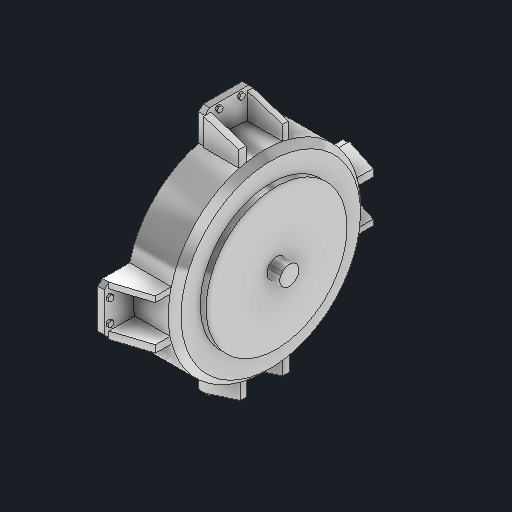
# Autodesk Inventor part: Bauteil1
Saved by Autodesk Inventor 2027.1 (Build 311270010, 270A)
## iProperties
Part Number: Bauteil1
Material: Generisch
Document SubType Name: Modellieren
Designer: Asus
Density: 1 g/cm^3
Appearance: Chrom - poliert
Author: Asus
Autodesk Inventor part; units mm, degrees
ref_plane "YZ-Ebene" through (0, 0, 0) normal (1, 0, 0) x (0, 1, 0)
ref_plane "XZ-Ebene" through (0, 0, 0) normal (0, 1, 0) x (-1, 0, 0)
sketch "Skizze1" plane through (0, 0, 0) normal (0, 0, 1) x (1, 0, 0)
  circle A0 centre (0, 0) radius 150
  dimension "d0" = 300
  constraints: 1 centre point, 1 coincident
  measures "d0" diameter of A0
extrude "Extrusion1" add sketch "Skizze1" along normal blind 75
chamfer "Fasen1" distance 10 angle 45 1 edges at (-150, 0, 75)
sketch "Skizze2" plane through (0, 0, 0) normal (0, 0, 1) x (1, 0, 0)
  circle A0 centre (0, 0) radius 150 projected
  line L0 (-37.5, 194.6569) -> (37.5, 194.6569)
  line L1 (37.5, 194.6569) -> (37.5, 145.2369)
  line L2 (-37.5, 145.2369) -> (-37.5, 194.6569)
  point P0 (0, 194.6569)
  dimension "d6" = 75
  dimension "d7" = 49.42
  constraints: 6 end point, 2 point on circle, 1 horizontal, 1 midpoint, 1 parallel, 1 perpendicular, 1 vertical alignment
  measures "d6" distance of L0.start L0.end
  measures "d7" distance of L0.end L1.end
extrude "Extrusion2" add sketch "Skizze2" along normal blind 10 contours A0 L2 L0 L1
chamfer "Fasen2" distance 7 angle 45 1 edges at (37.5, 194.6569, 5) measured on face at (37.5, 194.1569, 5)
chamfer "Fasen3" distance 7 angle 45 1 edges at (-37.5, 194.6569, 5) measured on face at (-37.5, 194.1569, 5)
sketch "Skizze3" plane through (-37.5, 145.2369, 0) normal (-1, 0, 0) x (0, 0, 1)
  line L0 (0, 42.42) -> (10, 42.42) projected
  line L1 (0, 42.42) -> (0, 0) projected
  line L2 (10, 0) -> (0, 0) projected
  line L3 (10, 42.42) -> (10, 0) projected
  line L4 (10, 0) -> (65, 0)
  line L5 (75, -10.3527) -> (75, -280.1211) construction
  line L6 (65, -290.4738) -> (0, -290.4738) construction
  line L7 (0, -290.4738) -> (0, 0) construction
  line L8 (0, 0) -> (0, 42.42) construction
  line L9 (0, 42.42) -> (10, 42.42) construction
  line L10 (10, 42.42) -> (10, 0) construction
  line L11 (10, 0) -> (65, 0) construction
  line L12 (10, 0) -> (0, 0) construction
  line L13 (65, -295.2369) -> (65, 4.7631) construction
  line L14 (65, 0) -> (65, 24.74)
  line L15 (65, 24.74) -> (10, 42.42)
  point P0 (0, -145.2369)
  dimension "d16" = 17.68
  constraints: 6 end point, 1 horizontal, 1 point on line, 1 vertical, 2 other
  measures "d16" vertical distance of L0.end L14.end
extrude "Extrusion3" add sketch "Skizze3" against normal blind 9 contours L15 L14 L4 L3
ref_plane "Arbeitsebene1" through (0, 145.2369, 0) normal (-1, 0, 0) x (0, 0, 1)
mirror "Spiegeln1" about plane through (0, 145.2369, 0) normal (-1, 0, 0) of "Extrusion3"
sketch "Skizze4" plane through (-37.5, 145.2369, 0) normal (-1, 0, 0) x (0, 0, 1)
  line L0 (0, 42.42) -> (10, 42.42) projected
  line L1 (0, 42.42) -> (0, 0) projected
  line L2 (65, 0) -> (0, 0) projected
  line L3 (65, 0) -> (65, 24.74) projected
  line L4 (65, 24.74) -> (10, 42.42) projected
  line L5 (10, 42.42) -> (10, 2.0307) projected
  line L6 (10, 42.42) -> (10, 0)
  line L7 (65, 0) -> (0, 0) projected
  point P0 (0, -145.2369)
  constraints: 2 end point, 2 point on line, 1 perpendicular
extrude "Extrusion4" add sketch "Skizze4" along normal blind 2.3128 contours L4 L3 L2 L6 L5
sketch "Skizze5" plane through (0, 0, 10) normal (0, 0, 1) x (1, 0, 0)
  line L0 (28.5, 187.6569) -> (37.5, 187.6569) construction
  line L1 (30.5, 194.6569) -> (37.5, 187.6569) construction
  line L2 (-30.5, 194.6569) -> (30.5, 194.6569) construction
  line L3 (-37.5, 187.6569) -> (-30.5, 194.6569) construction
  line L4 (-39.8128, 187.6569) -> (-37.5, 187.6569) construction
  line L5 (-39.8128, 145.2369) -> (-39.8128, 187.6569) construction
  line L6 (-37.5, 145.2369) -> (-39.8128, 145.2369) construction
  arc A0 (-37.5, 145.2369) -> (37.5, 145.2369) centre (0, 0) ccw construction
  line L7 (37.5, 187.6569) -> (37.5, 145.2369) construction
  line L8 (28.5, 147.2676) -> (28.5, 187.6569) construction
  arc A1 (28.5, 147.2676) -> (-28.5, 147.2676) centre (0, 0) ccw construction
  line L9 (-28.5, 147.2676) -> (-28.5, 187.6569) construction
  line L10 (-28.5, 187.6569) -> (-37.5, 187.6569) construction
  line L11 (-37.5, 187.6569) -> (-37.5, 145.2369) construction
  line L12 (-14.85, 183.5177) -> (-19.63, 183.5177)
  line L13 (-19.63, 183.5177) -> (-22.02, 187.6573)
  line L14 (-22.02, 187.6573) -> (-19.63, 191.7969)
  line L15 (-19.63, 191.7969) -> (-14.85, 191.7969)
  line L16 (-14.85, 191.7969) -> (-12.46, 187.6573)
  line L17 (-12.46, 187.6573) -> (-14.85, 183.5177)
  line L18 (14.85, 183.5177) -> (12.46, 187.6573)
  line L19 (12.46, 187.6573) -> (14.85, 191.7969)
  line L20 (14.85, 191.7969) -> (19.63, 191.7969)
  line L21 (19.63, 191.7969) -> (22.02, 187.6573)
  line L22 (22.02, 187.6573) -> (19.63, 183.5177)
  line L23 (19.63, 183.5177) -> (14.85, 183.5177)
  line L24 (0, 194.6569) -> (0, 150) construction
  point P0 (-17.24, 187.6573)
  point P1 (17.24, 187.6573)
  point P2 (17.24, 191.7969)
  dimension "d21" = 2.86
  dimension "d22" = 17.24
  dimension "d23" = 9.56
  constraints: 26 end point, 2 horizontal, 2 midpoint, 1 collinear, 1 point on circle, 1 point on line, 1 symmetric about line, 26 other
  measures "d21" distance between parallel lines of L2 L15
  measures "d22" distance from line of L24 point (-17.24, 187.657)
  measures "d23" distance of L21.end L18.end
extrude "Extrusion5" add sketch "Skizze5" along normal blind 3.5
pattern_circular "Runde Anordnung1" count 4 over 360 about axis through (0, 0, 0) along (0, 0, 1) of "Extrusion2", "Fasen2", "Fasen3", "Extrusion3", "Spiegeln1", "Extrusion4", "Extrusion5"
sketch "Skizze6" plane through (0, 0, 75) normal (0, 0, 1) x (1, 0, 0)
  arc A0 (37.5, -145.2369) -> (145.2369, -37.5) centre (0, 0) ccw construction
  circle A1 centre (0, 0) radius 140 construction
  arc A2 (70, -121.2436) -> (120.5039, -71.2658) centre (0, 0) ccw
  line L0 (70, -121.2436) -> (-49.7795, 86.2206) construction
  line L1 (-30.5, -194.6569) -> (30.5, -194.6569) projected
  line L2 (0, -194.6569) -> (0, 194.6569)
  line L3 (30.5, 194.6569) -> (-30.5, 194.6569) projected
  line L4 (-272.5196, 0) -> (272.5196, 0) projected
  arc A3 (80, -138.5641) -> (137.7187, -81.4466) centre (0, 0) ccw
  line L5 (0, 0) -> (120.5039, -71.2658) construction
  line L6 (80, -138.5641) -> (70, -121.2436)
  line L7 (137.7187, -81.4466) -> (120.5039, -71.2658)
  dimension "d29" = 60
  dimension "d30" = 29.4
  dimension "d31" = 20
  constraints: 11 end point, 4 point on circle, 2 centre point, 2 coincident, 2 midpoint, 2 point on line, 1 collinear, 2 other
  measures "d29" angle of L4 L0
  measures "d30" angle of L5 L0
extrude "Extrusion6" cut sketch "Skizze6" against normal blind 60
sketch "Skizze7" plane through (0, 0, 75) normal (0, 0, 1) x (1, 0, 0)
  circle A0 centre (0, 0) radius 110
  dimension "d34" = 220
  constraints: 1 centre point, 1 coincident
  measures "d34" diameter of A0
extrude "Extrusion7" add sketch "Skizze7" along normal blind 9
sketch "Skizze8" plane through (0, 0, 84) normal (0, 0, 1) x (1, 0, 0)
  circle A0 centre (0, 0) radius 15
  dimension "d37" = 30
  constraints: 1 centre point, 1 coincident
  measures "d37" diameter of A0
extrude "Extrusion8" add sketch "Skizze8" along normal blind 20
ref_plane "Arbeitsebene2" through (-145.2369, 0, 0) normal (0, -1, 0) x (0, 0, 1)
ref_plane "Arbeitsebene3" through (0, -145.2369, 0) normal (1, 0, 0) x (0, 0, 1)
ref_plane "Arbeitsebene4" through (145.2369, 0, 0) normal (0, 1, 0) x (0, 0, 1)
